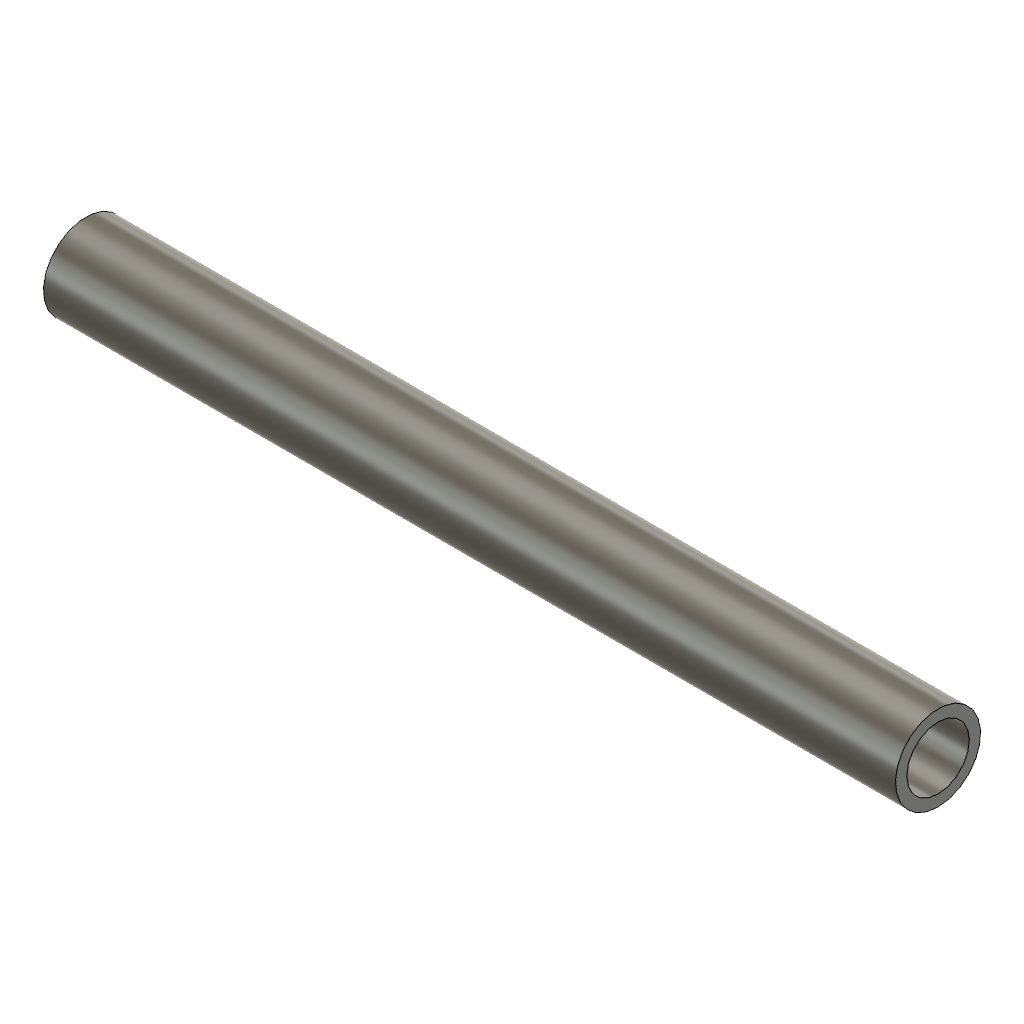
hollow (Autodesk Fusion 360 design; units mm, degrees)
part number: 2026-10-20-20-24-04-598
Autodesk Fusion 360 part; units mm, degrees
sketch "Sketch1" plane through (0, 0, 0) normal (0, 0, 1) x (1, 0, 0)
  line L0 (0, 0) -> (60, 0)
pipe "ProbePipe" add diameter 6 wall 0.8 path "Sketch1" along L0
